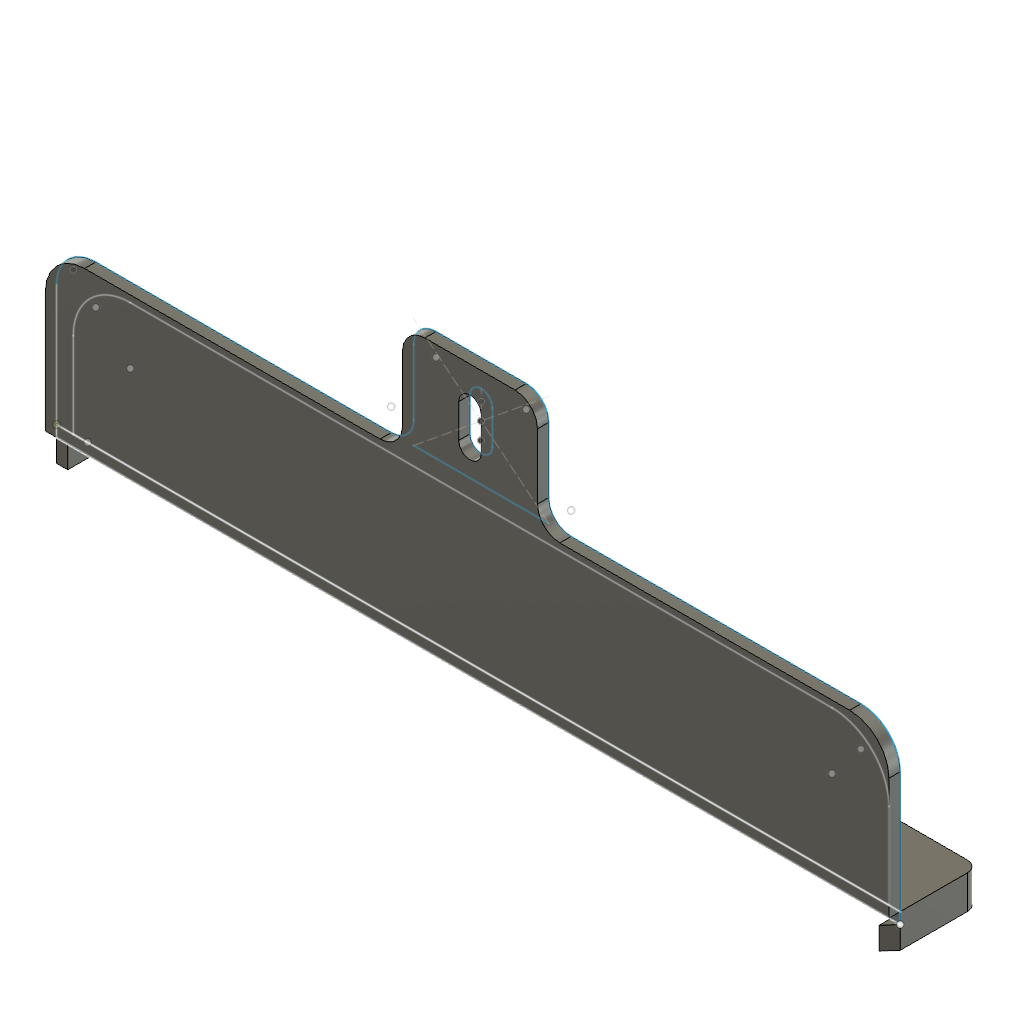
APCIE Clamp (Autodesk Fusion 360 design; units mm, degrees)
part number: 2026-10-18-17-04-03-279
Autodesk Fusion 360 part; units mm, degrees
sketch "Sketch1" plane through (0, 0, 0) normal (0, 0, 1) x (1, 0, 0)
  arc A0 (-75.9649, 146.806) -> (-71.9597, 146.806) centre (-73.9623, 146.806) ccw
  line L0 (-75.9649, 152.806) -> (-75.9649, 146.806)
  line L1 (-146.6698, 126.6434) -> (-146.6698, 111.4034)
  line L2 (-71.9597, 146.806) -> (-71.9597, 152.806)
  arc A1 (-71.9597, 152.806) -> (-75.9649, 152.806) centre (-73.9623, 152.806) ccw
  arc A2 (-136.5098, 136.8034) -> (-146.6698, 126.6434) centre (-136.5098, 126.6434) ccw
  line L3 (-11.4148, 136.8034) -> (-136.5098, 136.8034)
  line L4 (-73.9623, 144.8034) -> (-73.9623, 154.8086) construction
  line L5 (-146.6698, 111.4034) -> (-1.2548, 111.4034)
  arc A3 (-1.2548, 126.6434) -> (-11.4148, 136.8034) centre (-11.4148, 126.6434) ccw
  line L6 (-1.2548, 111.4034) -> (-1.2548, 126.6434)
  line L7 (-146.6698, 111.4034) -> (-149.6698, 111.4034) construction
  line L8 (-149.6698, 111.4034) -> (-149.6698, 109.4034) construction
  line L9 (-149.6698, 109.4034) -> (0.7452, 109.4034)
  line L10 (-149.6698, 109.4034) -> (0.7452, 109.4034)
  line L11 (0.7452, 109.4034) -> (0.7452, 111.4034)
  line L12 (0.7452, 111.4034) -> (-149.6698, 111.4034)
  line L13 (-149.6698, 111.4034) -> (-149.6698, 109.4034)
  line L14 (0.7452, 111.4034) -> (-149.6698, 111.4034)
  line L15 (-149.6698, 111.4034) -> (-149.6698, 133)
  line L16 (-57.9246, 140) -> (-6.2548, 140)
  line L17 (0.7452, 133) -> (0.7452, 111.4034)
  line L18 (-86, 140) -> (-61.9246, 140)
  line L19 (-61.9246, 144) -> (-61.9246, 155.612)
  line L20 (-65.9246, 159.612) -> (-82, 159.612)
  line L21 (-86, 155.612) -> (-86, 144)
  line L22 (-86, 140) -> (-61.9246, 159.612) construction
  line L23 (-61.9246, 140) -> (-86, 159.612) construction
  arc A4 (0.7452, 133) -> (-6.2548, 140) centre (-6.2548, 133) ccw
  arc A5 (-142.6698, 140) -> (-149.6698, 133) centre (-142.6698, 133) ccw
  arc A6 (-61.9246, 155.612) -> (-65.9246, 159.612) centre (-65.9246, 155.612) ccw
  arc A7 (-61.9246, 144) -> (-57.9246, 140) centre (-57.9246, 144) ccw
  line L24 (-90, 140) -> (-142.6698, 140)
  arc A8 (-82, 159.612) -> (-86, 155.612) centre (-82, 155.612) ccw
  arc A9 (-90, 140) -> (-86, 144) centre (-90, 144) ccw
  point P0 (-144.1298, 111.4086)
  point P1 (-146.6698, 136.8034)
  point P2 (-73.9623, 149.806)
  dimension "d1" = 145.415
  dimension "d2" = 25.4
  dimension "d3" = 10.16
  dimension "d4" = 4.0052
  dimension "d5" = 3
  dimension "d6" = 2
  dimension "d8" = 8
  dimension "d9" = 6
  dimension "d14" = 2
  dimension "d23" = 7
  dimension "d25" = 4
  constraint horizontal L5
  constraint vertical L6
  constraint horizontal L3
  constraint vertical L1
  constraint tangent A3 L6
  constraint tangent L3 A3
  constraint coincident P1 L3
  constraint coincident P1 L1
  constraint tangent A2 L3
  constraint tangent L1 A2
  constraint equal A2 A3
  constraint tangent L2 A1
  constraint tangent L0 A1
  constraint parallel L0 L2
  constraint tangent A0 L0
  constraint tangent A0 L2
  constraint coincident L4.start A0
  constraint coincident L4.end A1
  constraint coincident A1.centre L4
  constraint coincident A0.centre L4
  constraint perpendicular L3 L4
  constraint perpendicular L1 L7
  constraint perpendicular L7 L8
  constraint horizontal L9
  constraint horizontal L10
  constraint vertical L11
  constraint horizontal L12
  constraint vertical L13
  constraint horizontal L14
  constraint vertical L15
  constraint horizontal L16
  constraint vertical L17
  constraint horizontal L18
  constraint perpendicular L18 L19
  constraint parallel L18 L20
  constraint parallel L19 L21
  constraint coincident L22 P2
  constraint coincident L23 P2
  constraint coincident L16 L18.start
  constraint midpoint L4 P2
  constraint tangent L17 A4
  constraint tangent L16 A4
  constraint tangent L15 A5
  constraint equal A4 A5
  constraint coincident L22.end L20
  constraint coincident L22.end L19
  constraint tangent L20 A6
  constraint coincident L18.end L19
  constraint coincident L16 A5.start
  constraint tangent L16 A7
  constraint coincident L23.end L20
  constraint coincident L23.end L21
  constraint tangent L20 A8
  constraint tangent L21 A8
  constraint coincident L18.start L21
  constraint coincident L18.start L24
  constraint tangent L21 A9
  constraint tangent L24 A9
  constraint equal A6 A8
  constraint equal A7 A9
  constraint coincident L7.end L8.start
  measures "d1" distance of L1.end L5.end
  measures "d2" distance of L1.end P1
  measures "d3" radius of A3
  measures "d4" diameter of A1
  measures "d5" distance of L1.end L7.end
  measures "d6" distance of L7.end L8.end
  measures "d8" distance of L4.start L3
  measures "d9" distance of A1.centre A0.centre
  measures "d14" distance of L8.end L7.end
  measures "d23" radius of A4
  measures "d25" radius of A9
extrude "Extrude1" add sketch "Sketch1" along normal blind 2 contours L1 A2 L3 L5 A3 L6 L12 L14 | L1 A2 L3 A3 L6 L12 L14 L15 L16 L17 L19 L20 L21 A4 A5 A6 A7 L24 A8 A9
extrude "Extrude2" add sketch "Sketch1" against normal blind 14 contours L5 L9 L10 L11 L12 L13 L14
fillet "Fillet1" radius 2 2 edges at (-149.6698, 110.4034, -14) (0.7452, 110.4034, -14)
sketch "Sketch2" plane through (0, 109.4034, 0) normal (0, -1, 0) x (1, 0, 0)
  arc A0 (-1.2548, -14) -> (0.7452, -12) centre (-1.2548, -12) ccw
  line L0 (0.7452, -12) -> (0.7452, 0)
  line L1 (-149.6698, 0) -> (-149.6698, -12)
  arc A1 (-149.6698, -12) -> (-147.6698, -14) centre (-147.6698, -12) ccw
  line L2 (-147.6698, -14) -> (-1.2548, -14)
  line L3 (-149.6698, 0) -> (-147.6698, 0)
  line L4 (-147.6698, 0) -> (-147.6698, -9)
  line L5 (-145.6698, -11) -> (-3.0489, -11)
  line L6 (-1.0489, -9) -> (-1.0489, 2)
  line L7 (0.7452, 0) -> (-1.0489, 2)
  arc A2 (-3.0489, -11) -> (-1.0489, -9) centre (-3.0489, -9) ccw
  arc A3 (-147.6698, -9) -> (-145.6698, -11) centre (-145.6698, -9) ccw
  line L8 (0.7452, 0) -> (-149.6698, 0)
  dimension "d19" = 2
  dimension "d20" = 2
  constraint coincident L1.start L3.start
  constraint perpendicular L1 L3
  constraint perpendicular L5 L6
  constraint coincident L0.end L7.start
  constraint vertical L6
  constraint tangent L5 A2
  constraint tangent L6 A2
  constraint tangent L4 A3
  constraint tangent L5 A3
  constraint equal A2 A3
  measures "d19" distance of L1.start L3.end
  measures "d20" radius of A2
extrude "Extrude3" add sketch "Sketch2" along normal blind 4 contours A0 L0 L1 A1 L2 L3 L4 L5 L6 A2 A3 L8 | L6 L7 L8
